removable-lid (Autodesk Fusion 360 design; units mm, degrees)
part number: 2026-11-27-21-18-04-278
Autodesk Fusion 360 part; units mm, degrees
sketch "Sketch1" plane through (0, 0, 0) normal (0, 1, 0) x (1, 0, 0)
  line L0 (-70, 200) -> (70, 200)
  line L1 (70, 200) -> (70, -200)
  line L2 (70, -200) -> (-70, -200)
  line L3 (-70, -200) -> (-70, 200)
  line L4 (-70, 200) -> (70, -200) construction
  line L5 (70, 200) -> (-70, -200) construction
  dimension "d1" = 140
  dimension "d2" = 400
  constraint horizontal L0
  constraint perpendicular L0 L1
  constraint parallel L0 L2
  constraint parallel L1 L3
  constraint coincident L4 origin
  constraint coincident L5 origin
  measures "d1" distance of L1.end L2.end
extrude "Extrude1" add sketch "Sketch1" along normal blind 3
